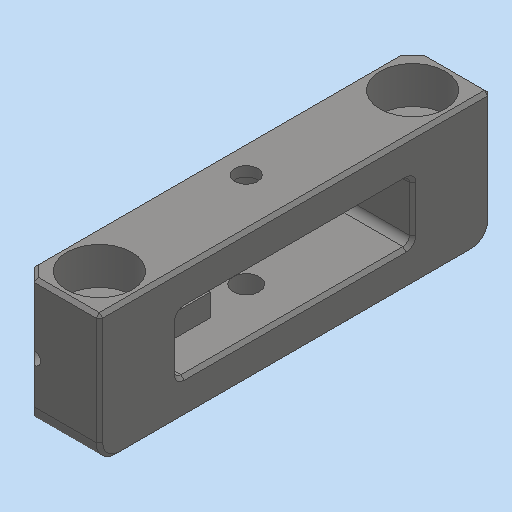
# Autodesk Inventor part: MM0948AN130_G01_108
Saved by Autodesk Inventor 2023.3 (Build 273359000, 359)
## iProperties
RuleStatus: InUse
Created: 2023-03-23
Part Number: MM0948AN130_G01_108
Material: 1.2379 X155CrVMo12-1
Description: =<RBPARTNOTITLE2>
Document SubType Name: Modeling
Designer: ric7an
Mass: 69.3122 g
Surface Area: 56.4721 cm^2
Volume: 8.82958 cm^3
Density: 7.85 g/cm^3
Appearance: Stahl - rostfrei AnP
AnP_Kategorie: 1
AnP_Material: =<Material>
MaxAbmaße: 20 x 60 x 12 (FM)
AnP_TemplVers: 20200821
RBDOCUMENTTYPE: DRF
RBDOCUMENTVERSION: 00
RBDRAWINGMAINSCALE: 1:1
RBDRAWINGMISSINGSPEC: --
RBDRAWINGVOLUME: --
RBDSV1: 0850
RBGBEDGESIN1: +0,5
RBGBEDGESIN2: +0,2
RBGBEDGESOUT1: -0,3
RBGBEDGESOUT2: -0,1
RBMATERIAL: =<Material>
RBMATMEETS: --
RBMATNO: =<Part Number>
RBPARTMADEOF: 20 x 60 x 12 (FM)
RBPARTNO: SIEHE MNR
RBPARTNOTITLE1: manufactured part
RBPARTNOTITLE2: Anfertigungsteil
RBPARTSAFETYINDICATOR: --
RBSURFACE: vaccum hardened 58 HRC ± 1
RBSURFACE2: vakuumgehaertet 58 HRC ± 1
RBZEDGESNORM: ISO13715:2002-06
RBZGENDIMCLASS: m
RBZGENDIMNORM: ISO 2768-1:1989-11
RBZGENGEOCLASS: H
RBZGENGEONORM: ISO 2768-2:1989-11
RBZSURFACENORM: ISO13D2:2002-02
RBZTOLERANCENORM: ISO 14405-1:2010-12
AnP_Kommentar_aktuell: =<Comments>
AnP_Material_aktuell: =<Material>
Author: FH/Wi
Keywords: =<RBPARTMADEOF>
Comments: =<RBSURFACE2>
Revision Number: 01
Autodesk Inventor part; units mm, degrees
ref_plane "YZ Plane" through (0, 0, 0) normal (1, 0, 0) x (0, 1, 0)
ref_plane "XZ Plane" through (0, 0, 0) normal (0, 1, 0) x (-1, 0, 0)
ref_plane "XY Plane" through (0, 0, 0) normal (0, 0, 1) x (1, 0, 0)
sketch "Skizze1" plane through (0, 0, 0) normal (0, 0, 1) x (1, 0, 0)
  line L0 (-6, 60) -> (6, 60)
  line L1 (6, 60) -> (6, 0)
  line L2 (6, 0) -> (-6, 0)
  line L3 (-6, 0) -> (-6, 60)
  line L4 (0, 72) -> (0, -12) projected
  line L5 (-8.4, 0) -> (8.4, 0) projected
  point P0 (0, 0)
  dimension "d0" = 12
  dimension "d1" = 60
  constraints: 8 end point, 2 parallel, 1 collinear, 1 horizontal, 1 perpendicular, 1 other
  measures "d0" distance of L0.start L0.end
  measures "d1" distance of L0.end L1.end
extrude "Extrusion1" add sketch "Skizze1" along normal mid plane 20
sketch "Skizze2" plane through (6, 0, -10) normal (1, 0, 0) x (0, 0, -1)
  line L0 (-14.5, 48) -> (-5.5, 48)
  line L1 (-5.5, 48) -> (-5.5, 12)
  line L2 (-5.5, 12) -> (-14.5, 12)
  line L3 (-14.5, 12) -> (-14.5, 48)
  line L4 (0, 60) -> (-20, 60) projected
  line L5 (-20, 0) -> (-20, 60) projected
  line L6 (0, 0) -> (-20, 0) projected
  line L7 (0, 60) -> (0, 0) projected
  line L8 (-10, -12) -> (-10, 72) projected
  point P0 (-10, 0)
  point P1 (-5.5, 30)
  point P2 (0, 30)
  dimension "d4" = 9
  dimension "d5" = 36
  constraints: 8 end point, 2 midpoint, 2 parallel, 1 horizontal, 1 horizontal alignment, 1 perpendicular, 1 other
  measures "d4" distance of L1.end L2.end
  measures "d5" distance of L0.end L1.end
extrude "Extrusion2" cut sketch "Skizze2" against normal through all contours L0 L8 L2 L3 | L0 L1 L2 L8
sketch "Skizze3" plane through (0, 0, -10) normal (0, 0, -1) x (-1, 0, 0)
  line L0 (6, 60) -> (-6, 60) projected
  line L1 (-6, 12) -> (6, 12) projected
  line L2 (6, 0) -> (6, 60) projected
  point P0 (1.5, 30)
  dimension "d34" = 18
  dimension "d35" = 4.5
  measures "d34" distance from line of L1 point (1.5, 30)
  measures "d35" distance from line of L2 point (1.5, 30)
hole "Bohrung1" at (-1.5, 30, -10) direction (0, 0, 1) diameter 3.5 end through all counterbore diameter 4 counterbore depth 18.5
sketch "Skizze6" plane through (6, 0, 10) normal (1, 0, 0) x (0, 0, -1)
  line L0 (14.5, 12) -> (5.5, 12) projected
  line L1 (10, -12) -> (10, 72) projected
  line L2 (11.7, 12) -> (8.3, 12)
  line L3 (8.3, 12) -> (8.3, 20)
  line L4 (8.3, 20) -> (11.7, 20)
  line L5 (11.7, 20) -> (11.7, 12)
  line L6 (5.5, 12) -> (5.5, 48) projected
  point P0 (10, 0)
  dimension "d19" = 8
  dimension "d57" = 2.8
  constraints: 8 end point, 2 parallel, 1 horizontal, 1 perpendicular, 1 point on line, 1 other
  measures "d19" distance of L4.end L2.start
  measures "d57" distance between parallel lines of L3 L6
extrude "Extrusion4" add sketch "Skizze6" against normal up to surface (12 mm away)
sketch "Skizze7" plane through (6, 20, 1.7) normal (0, 1, 0) x (1, 0, 0)
  line L0 (-6, 15.7) -> (-6, -12.3) projected
  line L1 (0, 3.4) -> (-12, 3.4) projected
  line L2 (-12, 3.4) -> (-12, 0) projected
  point P0 (-6, 1.7)
  point P1 (-10, 2.2)
  point P2 (-12, 1.7)
  dimension "d36" = 2
  dimension "d58" = 0.5
  constraints: 1 midpoint
  measures "d36" distance from line of point (-10, 2.2) L2
  measures "d58" vertical distance of point (-12, 1.7) point (-10, 2.2)
hole "Bohrung2" at (-4, 20, -0.5) direction (0, -1, 0) diameter 1 end through all
sketch "Skizze10" plane through (-6, 0, 10) normal (0, -1, 0) x (1, 0, 0)
  circle A0 centre (2, -10.5) radius 0.5 projected
  point P0 (6, -10)
  constraints: 1 coincident
hole "Bohrung4" at (-4, 0, -0.5) direction (0, 1, 0) diameter 2 depth 15 tip angle 118
sketch "Skizze8" plane through (6, 20, 1.7) normal (0, 1, 0) x (1, 0, 0)
  line L0 (-12, 3.4) -> (-12, 0) projected
  line L1 (0, 0) -> (-12, 0) projected
  line L2 (0, 3.4) -> (0, 0) projected
  line L3 (0, 3.4) -> (-12, 3.4) projected
  line L4 (0, 3.4) -> (-3, 3.4)
  line L5 (-3, 3.4) -> (-3, 0)
  line L6 (-3, 0) -> (0, 0)
  line L7 (0, 0) -> (0, 3.4)
  point P0 (-6, 1.7)
  dimension "d31" = 3
  constraints: 8 end point, 2 parallel, 1 horizontal, 1 perpendicular, 1 point on line
  measures "d31" distance between parallel lines of L2 L5
extrude "Extrusion5" cut sketch "Skizze8" against normal up to surface (8 mm away) contours L3 L2 L1 L5
sketch "Skizze9" plane through (0, 0, 10) normal (0, 0, 1) x (1, 0, 0)
  line L0 (6, 60) -> (-6, 60) projected
  line L1 (-6, 0) -> (6, 0) projected
  point P0 (0, 0)
  point P1 (0, 54)
  point P2 (0, 6)
  point P3 (0, 60)
  point P4 (0, 0)
  dimension "d44" = 6
  dimension "d45" = 6
  constraints: 2 midpoint, 2 vertical alignment
  measures "d44" distance from line of point (0, 54) L0
  measures "d45" distance from line of L1 point (0, 6)
hole "Bohrung3" at (0, 54, 10) at (0, 6, 10) direction (0, 0, -1) diameter 5.5 end through all counterbore diameter 10 counterbore depth 5.7 clearance for "Inbusschraube ISO 4762  versenkt" size "M5" standard "ISO"
chamfer "Fase1" distance 2 angle 45 2 edges at (-6, 60, 0) (-6, 0, 0)
fillet "Rundung1" radius 1 6 edges at (0, 12, 4.5) (-1.5, 12, -1.7) (0, 12, -4.5) (-1.5, 12, 1.7) (0, 48, 4.5) (0, 48, -4.5)
fillet "Rundung3" radius 3 2 edges at (1, 60, -10) (1, 0, -10)
chamfer "Fase2" distance 0.5 angle 45 36 edges at (6, 48, 0) (6, 47.7071, -4.2071) (6, 30, -4.5) (6, 12.2929, -4.2071) (6, 12, 0) (6, 12.2929, 4.2071) (6, 30, 4.5) (6, 47.7071, 4.2071) (-6, 12.2929, 1.9929) (-6, 12, 3.1) (-6, 12.2929, 4.2071) (-6, 30, 4.5) (-6, 47.7071, 4.2071) (-6, 48, 0) (-6, 47.7071, -4.2071) (-6, 30, -4.5) (-6, 12.2929, -4.2071) (-6, 12, -3.1) (-6, 12.2929, -1.9929) (-6, 16.5, -1.7) (-6, 16.5, 1.7) (-6, 20, 0) (-6, 30, 10) (-6, 30, -10) (-6, 57.5073, -9.9568) (-6, 2.4927, -9.9568) (6, 30, 10) (6, 30, -10) (6, 0.8787, -9.1213) (6, 0, 1.5) (6, 59.1213, -9.1213) (6, 60, 1.5) (1, 60, 10) (-5, 59, 10) (-5, 1, 10) (1, 0, 10)
